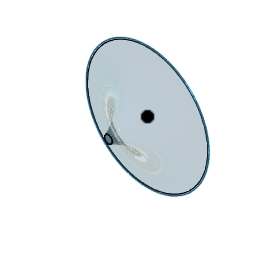
Hyperbolic Funnel_ (Autodesk Fusion 360 design; units mm, degrees)
Autodesk Fusion 360 part; units mm, degrees
note: some values were not read from the file. Set by a fixed rule: which face or edge a step refers to.
sketch "Sketch1" plane through (0, 0, 0) normal (0, 0, 1) x (1, 0, 0)
  arc A0 (-3.3524, -32) -> (-50, 0) centre (-50, -50) ccw
  line L0 (-50, 0) -> (50, 0) construction
  arc A1 (50, 0) -> (3.3524, -32) centre (50, -50) ccw
  line L1 (45, 0) -> (-50, 0)
  line L2 (0, -32) -> (0, 0)
  line L3 (1.0102, -32) -> (-3.3524, -32)
  line L4 (-3.3524, -32) -> (3.3524, -32)
  constraint tangent L0 A1
  constraint coincident L0 L1.start
  constraint tangent A0 L1
  constraint coincident L2.end origin
  constraint tangent A0 L2
  constraint perpendicular L2 L3
  constraint coincident L3 L2.start
sketch "Sketch2" plane through (0, 0, 0) normal (0, 1, 0) x (1, 0, 0)
  circle A0 centre (0, 0) radius 50
  constraint coincident A0.centre origin
sketch "Sketch3" plane through (0, 0, 0) normal (1, 0, 0) x (0, 1, 0)
sketch "Sketch4" plane through (0, 0, 0) normal (1, 0, 0) x (0, 1, 0)
  line L0 (0, 0) -> (-50, 0) construction
  constraint coincident L0.start origin
  constraint horizontal L0
revolve "Revolve1" add sketch "Sketch1" angle 360 about axis through (0, 0, 0) along (0, -1, 0)
shell "Shell1" thickness 0.01 removed faces 1 at (13.7706, 0, -13.2838)
sketch "Sketch5" plane through (0, -32, 0) normal (0, -1, 0) x (1, 0, 0)
  circle A0 centre (0, 0) radius 3.3524
  circle A1 centre (0, 0) radius 3
  dimension "d3" = 6
  constraint coincident A0.centre A1.centre
  measures "d3" diameter of A1
extrude "Extrude1" cut sketch "Sketch5" against normal up to surface (0.01 mm away) contours A1
